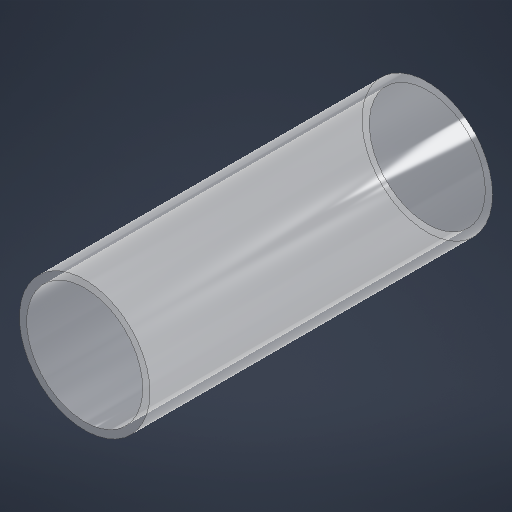
# Autodesk Inventor part: main_hull
Saved by Autodesk Inventor 2026.2 (Build 302298010, 298A)
## iProperties
Created: 2026-10-25
Part Number: main_hull
Material: Plastique PMMA
Document SubType Name: Modeling
Designer: User
Density: 1.188 g/cm^3
Appearance: Polycarbonate - Transparent
Author: User
Autodesk Inventor part; units mm, degrees
ref_plane "YZ Plane" through (0, 0, 0) normal (1, 0, 0) x (0, 1, 0)
ref_plane "XZ Plane" through (0, 0, 0) normal (0, 1, 0) x (-1, 0, 0)
ref_plane "XY Plane" through (0, 0, 0) normal (0, 0, 1) x (1, 0, 0)
sketch "Esquisse1" plane through (0, 0, 0) normal (0, 0, 1) x (1, 0, 0)
  circle A0 centre (0, 0) radius 50.8
  circle A1 centre (0, 0) radius 57.15
  dimension "d0" = 101.6
  dimension "d1" = 114.3
  constraints: 2 centre point, 1 coincident, 1 concentric
  measures "d0" diameter of A0
  measures "d1" diameter of A1
extrude "Extrusion1" add sketch "Esquisse1" along normal blind 300
equation "\"d0\" = D_int_main_hull"
equation "\"d1\" = D_ext_main_hull"
equation "\"d2\" = L_main_hull"
equation "\"L_main_hull\" = 300"
equation "\"D_int_main_hull\" = 101.6"
equation "\"D_ext_main_hull\" = 114.3"
